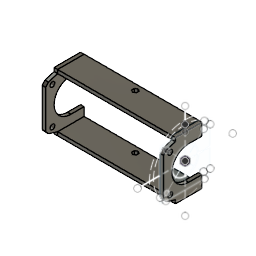
MotorHolder (Autodesk Fusion 360 design; units mm, degrees)
Autodesk Fusion 360 part; units mm, degrees
note: some values were not read from the file. Set by a fixed rule: which face or edge a step refers to.
sketch "Motor layout" plane through (0, 0, 0) normal (1, 0, 0) x (0, 1, 0)
  line L0 (21.15, 21.15) -> (-21.15, 21.15)
  line L1 (-21.15, 21.15) -> (-21.15, -21.15)
  line L2 (-21.15, -21.15) -> (21.15, -21.15)
  line L3 (21.15, -21.15) -> (21.15, 21.15)
  line L4 (21.15, 21.15) -> (-21.15, -21.15) construction
  line L5 (-21.15, 21.15) -> (21.15, -21.15) construction
  circle A0 centre (0, 0) radius 11
  circle A1 centre (-15.5, 15.5) radius 2
  circle A2 centre (-15.5, -15.5) radius 2
  circle A3 centre (15.5, -15.5) radius 2
  circle A4 centre (15.5, 15.5) radius 2
  line L6 (-16.15, 21.15) -> (-21.15, 16.15)
  line L7 (-21.15, -16.15) -> (-16.15, -21.15)
  line L8 (16.15, -21.15) -> (21.15, -16.15)
  line L9 (21.15, 16.15) -> (16.15, 21.15)
  circle A5 centre (0, 0) radius 30 construction
  circle A6 centre (0, 0) radius 26.611 construction
  line L10 (0, -40) -> (0, 40)
  line L11 (-40, 0) -> (40, 0)
  point P0 (0, 26.611)
  point P1 (0, 21.15)
  dimension "d1" = 42.3
  dimension "d2" = 22
  dimension "d3" = 4
  dimension "d5" = 360
  dimension "d6" = 31
  dimension "d7" = 5
  dimension "d9" = 360
  dimension "d10" = 60
  dimension "d11" = 80
  dimension "d12" = 80
  constraint horizontal L0
  constraint perpendicular L0 L1
  constraint parallel L0 L2
  constraint parallel L1 L3
  constraint coincident L4 A0.centre
  constraint coincident L5 A0.centre
  constraint coincident A0.centre A5.centre
  constraint equal L0 L3
  constraint coincident L5 A1.centre
  constraint coincident L0 L6.start
  constraint coincident L1 L6.end
  constraint perpendicular L5 L6
  constraint concentric A5 A6
  constraint coincident L6.start A6
  constraint midpoint L10 A0.centre
  constraint vertical L10
  constraint midpoint L11 A0.centre
  constraint perpendicular L3 L11
  constraint coincident A6 P0
  constraint coincident L10 P0
  constraint midpoint L0 P1
  measures "d1" distance of L0.start L0.end
  measures "d2" diameter of A0
  measures "d3" diameter of A1
  measures "d6" distance of A1.centre A4.centre
  measures "d7" distance of L1 L6.start
  measures "d10" diameter of A5
  measures "d11" distance of L10.start L10.end
  measures "d12" distance of L11.start L11.end
sketch "Adapter" plane through (0, 0, 0) normal (1, 0, 0) x (0, 1, 0)
  line L0 (21.15, 21.15) -> (-21.15, 21.15)
  circle A0 centre (0, 0) radius 26.611
  circle A1 centre (0, 0) radius 30
  circle A2 centre (15.5, 15.5) radius 2
  circle A3 centre (-15.5, 15.5) radius 2
  circle A4 centre (0, 0) radius 11
  line L1 (-21.15, 21.15) -> (-21.15, -21.15)
  line L2 (-21.15, 21.15) -> (21.15, -21.15)
  line L3 (21.15, 21.15) -> (-21.15, -21.15)
  line L4 (21.15, -21.15) -> (21.15, 21.15)
  line L5 (-21.15, -21.15) -> (21.15, -21.15)
  circle A5 centre (-15.5, -15.5) radius 2
  circle A6 centre (15.5, -15.5) radius 2
  line L6 (-11.1769, 21.15) -> (11.1769, 21.15)
  line L7 (11.1769, 21.15) -> (11.1769, 24.15)
  line L8 (11.1769, 24.15) -> (-11.1769, 24.15)
  line L9 (-11.1769, 24.15) -> (-11.1769, 21.15)
  line L10 (0, -40) -> (0, 40)
  line L11 (-11.1769, 21.15) -> (-18.8168, 18.8168)
  line L12 (-18.8168, 18.8168) -> (-21.15, 16.15)
  line L13 (-21.15, 16.15) -> (-21.15, -16.15)
  line L14 (-21.15, -16.15) -> (-18.8168, -18.8168)
  line L15 (-40, 0) -> (40, 0)
  line L16 (-11.1769, -21.15) -> (11.1769, -21.15)
  line L17 (11.1769, -24.15) -> (-11.1769, -24.15)
  line L18 (11.1769, -21.15) -> (11.1769, -24.15)
  line L19 (-11.1769, -24.15) -> (-11.1769, -21.15)
  line L20 (-16.15, -21.15) -> (-11.1769, -21.15)
  line L21 (11.1769, 21.15) -> (11.1769, -21.15)
  circle A7 centre (0, 0) radius 14
  line L22 (0, -14) -> (11.1769, -14)
  line L23 (0, 14) -> (11.1769, 14)
  line L24 (-11.1769, -21.15) -> (-18.8168, -18.8168)
  dimension "d13" = 3
  dimension "d14" = 3
  constraint horizontal L6
  constraint vertical L7
  constraint horizontal L8
  constraint vertical L9
  constraint coincident A0 L7.end
  constraint coincident L0 L6.start
  constraint symmetric L7 L9 L10
  constraint coincident A0 L11.end
  constraint coincident L2 L11.end
  constraint coincident L1 L12.end
  constraint coincident A0 L12.end
  constraint coincident A0 L13.end
  constraint coincident L1 L13.end
  constraint coincident L3 L14.end
  constraint coincident A0 L14.end
  constraint coincident A0 L20.start
  constraint coincident L5 L20.start
  constraint symmetric L6.start L15 L16.start
  constraint symmetric L6.end L15 L16.end
  constraint symmetric L7.end L15 L17.start
  constraint symmetric L8.end L15 L17.end
  constraint coincident A7 L22.start
  constraint coincident L10 L22.start
  constraint coincident L21 L22.end
  constraint tangent A7 L22
  constraint coincident A7 L23.start
  constraint coincident L10 L23.start
  constraint coincident L21 L23.end
  constraint tangent A7 L23
  measures "d13" distance of L6.end L7.end
extrude "Extrude1" add sketch "Adapter" along normal blind 3 contours L0 L6 L10 L21 L23 | L0 L6 L7 L8 L10 | L0 A3 L2 L6 L10 L11 A7 | L0 L6 L8 L9 L10 | A3 L1 L2 L12 L13 L15 A7 | L1 L3 A5 L13 L14 L15 A7 | L5 L10 L16 L17 L18 | L5 L10 L16 L21 L22 | L5 L10 L16 L17 L19 | L3 L5 A5 L10 L16 A7 L24 makes body 1
ref_plane "WorkPlane1" through (-96, 0, 0) normal (1, 0, 0) x (0, 1, 0)
ref_plane "WorkPlane2" through (-48, 0, 0) normal (1, 0, 0) x (0, 1, 0)
mirror "Mirror1" about plane through (-48, 0, 0) normal (1, 0, 0) of bodies 1 makes body 2
extrude "Extrude2" add sketch "Adapter" against normal up to surface (96 mm away) separate body contours L0 L6 L7 L8 L10 | L0 L6 L8 L9 L10 makes body 3
extrude "Extrude3" add sketch "Adapter" against normal up to surface (96 mm away) separate body contours L5 L10 L16 L17 L18 | L5 L10 L16 L17 L19 makes body 4
sketch "Sketch5" plane through (0, 0, 24.15) normal (0, 0, 1) x (-1, 0, 0)
  line L0 (96, -11.1769) -> (96, 11.1769)
  line L1 (96, 11.1769) -> (0, 11.1769)
  line L2 (0, 11.1769) -> (0, -11.1769)
  line L3 (0, -11.1769) -> (96, -11.1769)
  line L4 (48, -11.1769) -> (48, 11.1769)
  circle A0 centre (48, -6.1769) radius 2
  line L5 (48, -8.4863) -> (50, -7.3316)
  line L6 (50, -7.3316) -> (50, -5.0222)
  line L7 (50, -5.0222) -> (48, -3.8675)
  line L8 (48, -3.8675) -> (46, -5.0222)
  line L9 (46, -5.0222) -> (46, -7.3316)
  line L10 (46, -7.3316) -> (48, -8.4863)
  point P0 (48, -6.1769)
  point P1 (48, -6.1769)
  dimension "d24" = 4
  dimension "d25" = 5
  dimension "d26" = 4
  constraint midpoint L3 L4.start
  constraint midpoint L1 L4.end
  constraint coincident L4 P1
  constraint coincident P1 P0
  constraint parallel L4 L9
  measures "d24" diameter of A0
  measures "d25" distance of L4.start P1
  measures "d26" distance of L6 L9
extrude "Extrude4" cut sketch "Sketch5" against normal up to surface (48.3 mm away) contours L4 A0 L10 | L4 A0 L5 | L4 A0 L7 | L4 A0 L8 | L4 A0 | L4 A0 | A0 L5 L6 | A0 L9 L10 | A0 L6 L7 | A0 L8 L9 bodies 3 4
named bodies: "Right Adapter", "Left Adapter", "Front Belt", "Back Belt"
